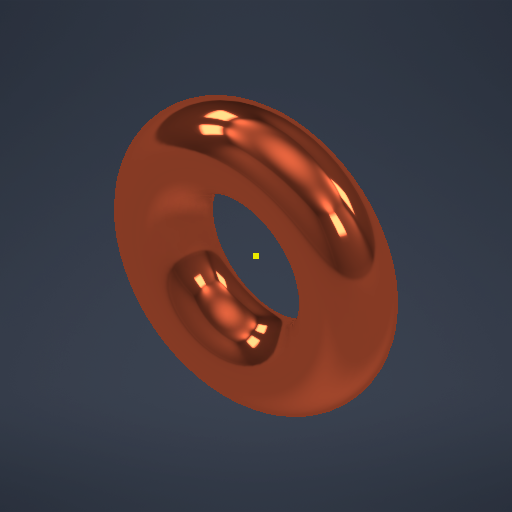
# Autodesk Inventor part: Copper coil
Saved by Autodesk Inventor 2026.2 (Build 302298010, 298A)
## iProperties
Created: 2026-10-06
Part Number: Copper coil
Material: Generisch
Document SubType Name: Modeling
Designer: denis
Mass: 49.348 g
Surface Area: 98.696 cm^2
Volume: 49.348 cm^3
Density: 1 g/cm^3
Appearance: Vorgabe
Author: denis
Autodesk Inventor part; units mm, degrees
ref_plane "YZ Plane" through (0, 0, 0) normal (1, 0, 0) x (0, 1, 0)
ref_plane "XZ Plane" through (0, 0, 0) normal (0, 1, 0) x (-1, 0, 0)
ref_plane "XY Plane" through (0, 0, 0) normal (0, 0, 1) x (1, 0, 0)
sketch "Skizze1" plane through (0, 0, 0) normal (0, 0, 1) x (1, 0, 0)
  point P0 (0, 0)
sketch "Skizze2" plane through (0, 0, 0) normal (0, 1, 0) x (-1, 0, 0)
  circle A0 centre (24.956, 1.4825) radius 10
  line L0 (0.3706, -6.239) -> (-0.3706, 6.239)
  line L1 (0, 0) -> (24.956, 1.4825) construction
  dimension "d0" = 20
  dimension "d1" = 25
  constraints: 4 end point, 1 centre point, 1 midpoint, 1 perpendicular
  measures "d0" diameter of A0
  measures "d1" distance of L1.start L1.end
revolve "Umdrehung1" add sketch "Skizze2" angle 360 about axis through (-0.3706, 0, -6.239) along (0.0593, 0, 0.9982)
